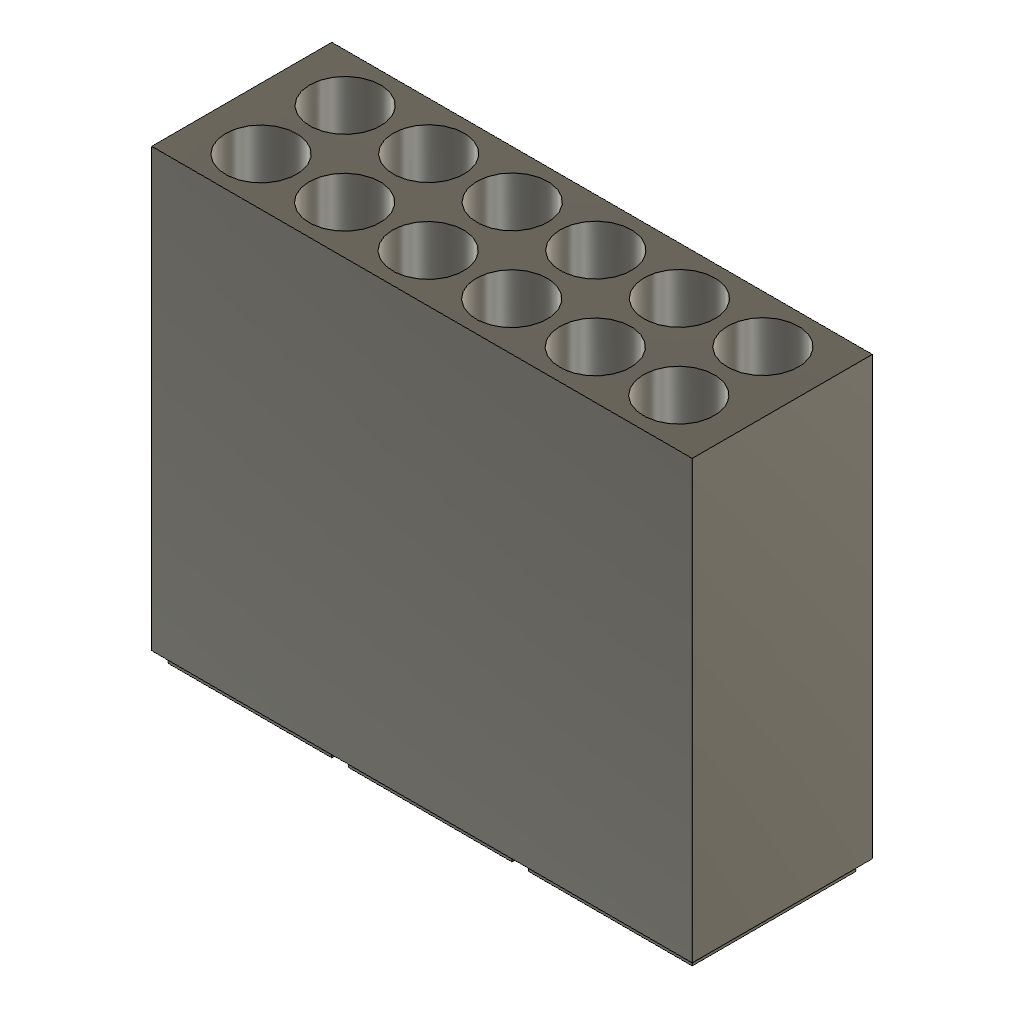
Pen Compartment (Autodesk Fusion 360 design; units mm, degrees)
part number: 2026-10-19-01-01-49-816
Autodesk Fusion 360 part; units mm, degrees
sketch "Sketch1" plane through (0, 0, 0) normal (0, 0, 1) x (1, 0, 0)
  line L0 (-51.45, 30) -> (47.55, 30)
  line L1 (47.55, 30) -> (47.55, -3)
  line L2 (47.55, -3) -> (-51.45, -3)
  line L3 (-51.45, -3) -> (-51.45, 30)
  circle A0 centre (-40.2, 21.2) radius 6.5
  circle A1 centre (-24.9, 21.2) radius 6.5
  circle A2 centre (-9.6, 21.2) radius 6.5
  circle A3 centre (-40.2, 5.8) radius 6.5
  circle A4 centre (5.7, 21.2) radius 6.5
  circle A5 centre (21, 21.2) radius 6.5
  circle A6 centre (36.3, 21.2) radius 6.5
  circle A7 centre (-40.2, 21.2) radius 6.5
  circle A8 centre (-24.9, 5.8) radius 6.5
  circle A9 centre (-9.6, 5.8) radius 6.5
  circle A10 centre (5.7, 5.8) radius 6.5
  circle A11 centre (21, 5.8) radius 6.5
  circle A12 centre (36.3, 5.8) radius 6.5
  point P0 (-24.9, 21.2)
  point P1 (-24.9, 21.2)
  point P2 (-24.9, 21.2)
  point P3 (-24.9, 21.2)
  dimension "d1" = 99
  dimension "d2" = 33
  dimension "d3" = 13
  dimension "d4" = 13
  dimension "d5" = 13
  dimension "d6" = 13
  dimension "d7" = 13
  dimension "d14" = 13
  dimension "d15" = 13
  dimension "d16" = 11.25
  dimension "d17" = 8.8
  dimension "d18" = 11.25
  dimension "d19" = 8.8
  dimension "d20" = 8.8
  dimension "d21" = 15.3
  dimension "d22" = 15.3
  dimension "d23" = 15.3
  dimension "d24" = 15.3
  dimension "d25" = 15.3
  dimension "d26" = 8.8
  dimension "d27" = 8.8
  dimension "d28" = 8.8
  dimension "d29" = 8.8
  dimension "d30" = 13
  dimension "d33" = 13
  dimension "d34" = 13
  dimension "d35" = 13
  dimension "d36" = 13
  dimension "d37" = 13
  dimension "d38" = 8.8
  dimension "d39" = 8.8
  dimension "d40" = 8.8
  dimension "d41" = 8.8
  dimension "d42" = 8.8
  dimension "d43" = 15.3
  dimension "d44" = 15.3
  dimension "d45" = 15.3
  dimension "d46" = 15.3
  dimension "d47" = 15.3
  constraint horizontal L0
  constraint vertical L1
  constraint horizontal L2
  constraint vertical L3
  measures "d1" distance of L1 L3
  measures "d2" distance of L0 L2
  measures "d3" diameter of A0
  measures "d4" diameter of A1
  measures "d5" diameter of A2
  measures "d6" diameter of A3
  measures "d7" diameter of A4
  measures "d14" diameter of A5
  measures "d15" diameter of A6
  measures "d16" distance of L3 A0.centre
  measures "d17" distance of L0 A0.centre
  measures "d18" distance of L3 A3.centre
  measures "d19" distance of L2 A3.centre
  measures "d20" distance of L0 P3
  measures "d21" distance of A0.centre P3
  measures "d22" horizontal distance of P3 A2.centre
  measures "d23" horizontal distance of A2.centre A4.centre
  measures "d24" horizontal distance of A4.centre A5.centre
  measures "d25" horizontal distance of A5.centre A6.centre
  measures "d26" distance of L0 A2.centre
  measures "d27" distance of L0 A4.centre
  measures "d28" distance of L0 A5.centre
  measures "d29" distance of L0 A6.centre
  measures "d30" diameter of A7
  measures "d33" diameter of A8
  measures "d34" diameter of A9
  measures "d35" diameter of A10
  measures "d36" diameter of A11
  measures "d37" diameter of A12
  measures "d38" distance of L2 A8.centre
  measures "d39" distance of L2 A9.centre
  measures "d40" distance of L2 A10.centre
  measures "d41" distance of L2 A11.centre
  measures "d42" distance of L2 A12.centre
  measures "d43" distance of A3.centre A8.centre
  measures "d44" distance of A8.centre A9.centre
  measures "d45" distance of A9.centre A10.centre
  measures "d46" distance of A10.centre A11.centre
  measures "d47" distance of A11.centre A12.centre
extrude "Extrude1" add sketch "Sketch1" along normal blind 80
sketch "Sketch2" plane through (0, 0, 0) normal (0, 0, -1) x (1, 0, 0)
  circle A0 centre (21, -5.8) radius 6.5
  circle A1 centre (5.7, -21.2) radius 6.5
  line L0 (47.55, 3) -> (-51.45, 3)
  line L1 (-51.45, 3) -> (-51.45, -30)
  line L2 (-51.45, -30) -> (47.55, -30)
  line L3 (47.55, -30) -> (47.55, 3)
  circle A2 centre (-24.9, -5.8) radius 6.5
  circle A3 centre (-24.9, -21.2) radius 6.5
  circle A4 centre (-40.2, -5.8) radius 6.5
  circle A5 centre (36.3, -5.8) radius 6.5
  circle A6 centre (21, -21.2) radius 6.5
  circle A7 centre (5.7, -5.8) radius 6.5
  circle A8 centre (-40.2, -21.2) radius 6.5
  circle A9 centre (36.3, -21.2) radius 6.5
  circle A10 centre (-9.6, -21.2) radius 6.5
  circle A11 centre (-9.6, -5.8) radius 6.5
  line L4 (-51.45, 3) -> (47.55, 3)
  line L5 (47.55, 3) -> (47.55, -30)
  line L6 (47.55, -30) -> (-51.45, -30)
  line L7 (-51.45, -30) -> (-51.45, 3)
  constraint horizontal L4
  constraint vertical L5
  constraint horizontal L6
  constraint vertical L7
  constraint coincident L2.end L3.start
  constraint coincident L0.end L1.start
extrude "Extrude2" cut sketch "Sketch2" against normal blind 3 contours A0 | A1 | L0 L1 L2 L3 L4 L5 L6 L7 | A2 | A3 | A4 | A5 | A6 | A7 | A8 | A9 | A10 | A11
extrude "Extrude3" add sketch "Sketch2" against normal blind 3 contours A0 | A1 | L0 L1 L2 L3 L4 L5 L6 L7 | A2 | A3 | A4 | A5 | A6 | A7 | A8 | A9 | A10 | A11
sketch "Sketch3" plane through (0, 0, 0) normal (0, 0, 1) x (1, 0, 0)
  line L0 (47.55, 30) -> (-51.45, 30)
  line L1 (-51.45, 30) -> (-51.45, -3)
  line L2 (-51.45, -3) -> (47.55, -3)
  line L3 (47.55, -3) -> (47.55, 30)
  line L4 (46.05, 28.5) -> (16.05, 28.5)
  line L5 (16.05, 28.5) -> (16.05, -1.5)
  line L6 (16.05, -1.5) -> (46.05, -1.5)
  line L7 (46.05, -1.5) -> (46.05, 28.5)
  line L8 (13.05, 28.5) -> (-16.95, 28.5)
  line L9 (-16.95, 28.5) -> (-16.95, -1.5)
  line L10 (-16.95, -1.5) -> (13.05, -1.5)
  line L11 (13.05, -1.5) -> (13.05, 28.5)
  line L12 (-19.95, 28.5) -> (-49.95, 28.5)
  line L13 (-49.95, 28.5) -> (-49.95, -1.5)
  line L14 (-49.95, -1.5) -> (-19.95, -1.5)
  line L15 (-19.95, -1.5) -> (-19.95, 28.5)
  dimension "d54" = 1.5
  dimension "d55" = 1.5
  dimension "d56" = 1.5
  dimension "d57" = 1.5
  dimension "d58" = 1.5
  dimension "d59" = 1.5
  dimension "d60" = 1.5
  dimension "d61" = 1.5
  dimension "d62" = 3
  dimension "d63" = 3
  dimension "d64" = 30
  dimension "d65" = 30
  dimension "d66" = 30
  dimension "d67" = 30
  constraint horizontal L0
  constraint vertical L1
  constraint horizontal L2
  constraint vertical L3
  constraint horizontal L4
  constraint vertical L5
  constraint horizontal L6
  constraint vertical L7
  constraint horizontal L8
  constraint vertical L9
  constraint horizontal L10
  constraint vertical L11
  constraint horizontal L12
  constraint vertical L13
  constraint horizontal L14
  constraint vertical L15
  measures "d54" distance of L3 L7
  measures "d55" distance of L0 L4
  measures "d56" distance of L2 L6
  measures "d57" distance of L0 L8
  measures "d58" distance of L2 L10
  measures "d59" distance of L2 L14
  measures "d60" distance of L0 L12
  measures "d61" distance of L1 L13
  measures "d62" distance of L5 L11
  measures "d63" distance of L9 L15
  measures "d64" distance of L5 L7
  measures "d65" distance of L9 L11
  measures "d66" distance of L13 L15
  measures "d67" distance of L4 L6
extrude "Extrude4" add sketch "Sketch3" against normal blind 3 contours L4 L5 L6 L7 | L8 L9 L10 L11 | L12 L13 L14 L15
chamfer "Chamfer1" distance 1 angle 45 3 faces at (26.05, 18.5, -3) (-6.95, 18.5, -3) (-29.95, 18.5, -3) tangent chain off
